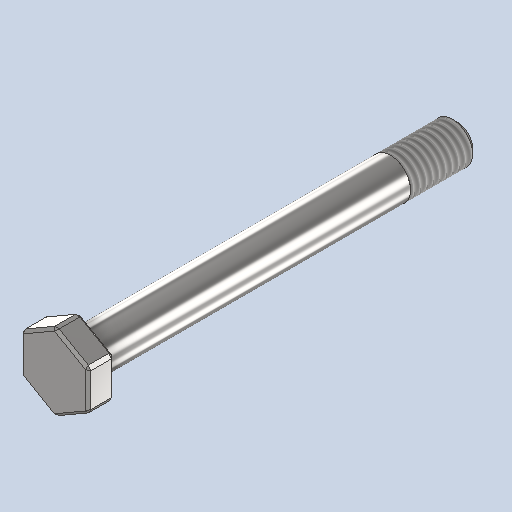
# Autodesk Inventor part: Anschweißlasche Schraube M8
Saved by Autodesk Inventor 2026.2 (Build 302298010, 298A)
## iProperties
Created: 2026-07-28
Part Number: Anschweißlasche Schraube M8
Material: Edelstahl
Document SubType Name: Modeling
Designer: moest
Density: 8 g/cm^3
Appearance: Halbpoliert
Author: moest
Autodesk Inventor part; units mm, degrees
ref_plane "YZ Plane" through (0, 0, 0) normal (1, 0, 0) x (0, 1, 0)
ref_plane "XZ Plane" through (0, 0, 0) normal (0, 1, 0) x (-1, 0, 0)
ref_plane "XY Plane" through (0, 0, 0) normal (0, 0, 1) x (1, 0, 0)
sketch "Skizze1" plane through (0, 0, 0) normal (0, 1, 0) x (-1, 0, 0)
  line L0 (0, -7.5056) -> (-6.5, -3.7528)
  line L1 (-6.5, -3.7528) -> (-6.5, 3.7528)
  line L2 (-6.5, 3.7528) -> (0, 7.5056)
  line L3 (0, 7.5056) -> (6.5, 3.7528)
  line L4 (6.5, 3.7528) -> (6.5, -3.7528)
  line L5 (6.5, -3.7528) -> (0, -7.5056)
  point P0 (0, 0)
  point P1 (0, 0)
  point P2 (3.25, 5.6292)
  dimension "d1" = 13
  constraints: 12 end point, 1 coincident, 1 midpoint, 13 other
  measures "d1" distance from line of L0 point (3.25, 5.629)
extrude "Extrusion1" add sketch "Skizze1" along normal blind 5
sketch "Skizze2" plane through (0, 5, 0) normal (0, 1, 0) x (1, 0, 0)
  circle A0 centre (0, 0) radius 3.9
  dimension "d4" = 7.8
  constraints: 1 centre point, 1 coincident
  measures "d4" diameter of A0
extrude "Extrusion2" add sketch "Skizze2" along normal blind 60
sketch "Skizze3" plane through (0, 65, 0) normal (0, 1, 0) x (1, 0, 0)
  circle A0 centre (0, 0) radius 3.9
  constraints: 1 centre point, 1 coincident
extrude "Extrusion3" add sketch "Skizze3" along normal blind 13 separate body
thread "Gewinde1" size "M8x1.25" class "6g" standard "ANSI Metric M Profile" full length
chamfer "Fasen1" distance 1 angle 45 1 edges at (-3.9, 78, 0)
chamfer "Fasen2" distance 0.5 angle 45 18 edges at (6.5, 5, 0) (3.25, 5, 5.6292) (6.5, 2.5, 3.7528) (3.25, 0, 5.6292) (-3.25, 0, 5.6292) (0, 2.5, 7.5056) (-3.25, 5, 5.6292) (-6.5, 2.5, 3.7528) (-6.5, 5, 0) (-3.25, 5, -5.6292) (-6.5, 2.5, -3.7528) (-3.25, 0, -5.6292) (-6.5, 0, 0) (0, 2.5, -7.5056) (3.25, 5, -5.6292) (3.25, 0, -5.6292) (6.5, 2.5, -3.7528) (6.5, 0, 0)
sketch "Skizze4" plane through (0, 0, 0) normal (1, 0, 0) x (0, 1, 0)
  line L0 (5, 3.9) -> (5, -3.9) projected
  line L1 (5, -3.9) -> (5, -2.5402)
  line L2 (5, -3.9) -> (5, -3.7)
  line L3 (5, -3.7) -> (5.5, -3.7)
  line L4 (5.5, -3.7) -> (5.7, -3.9)
  line L5 (5, -3.9) -> (65, -3.9) projected
  line L6 (5.7, -3.9) -> (5, -3.9)
  line L7 (-15.6, 0) -> (93.6, 0) projected
  point P0 (0, 0)
  dimension "d17" = 0.2
  dimension "d18" = 0.5
  dimension "d19" = 135
  constraints: 10 end point, 3 point on line, 1 collinear, 1 perpendicular
  measures "d17" distance of L0.end L2.end
  measures "d18" distance of L2.end L3.end
  measures "d19" angle of L3 L4
revolve "Umdrehung1" cut sketch "Skizze4" angle 360 about axis through (0, -10, 0) along (0, 1, 0) bodies 1
